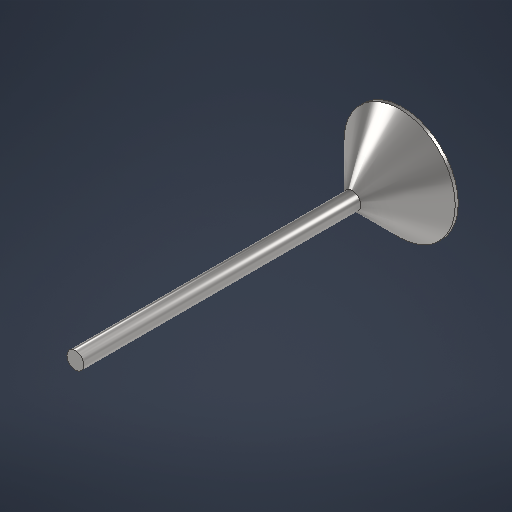
# Autodesk Inventor part: Intake_Valve
Saved by Autodesk Inventor 2027.1 (Build 311270010, 270A)
## iProperties
Created: 2026-10-17
Part Number: Intake_Valve
Material: Steel, Alloy
Document SubType Name: Modeling
Designer: kashyap
Density: 7.73 g/cm^3
Appearance: Semi-Polished
Mass: 71.2298 g
Surface Area: 41.0236 cm^2
Volume: 9.21472 cm^3
Material_Status: Assumed for this reconstruction
Author: kashyap
Autodesk Inventor part; units mm, degrees
derived "V6_Engine_Master.ipt"
ref_plane "Valve_Face_Plane" through (0, 0, 0) normal (0, 0, 1) x (1, 0, 0)
ref_plane "Valve_Margin_Plane" through (0, 0, 1) normal (0, 0, 1) x (1, 0, 0)
sketch "SK_Head" plane through (0, 0, 0) normal (0, 0, 1) x (1, 0, 0)
  circle A0 centre (0, 0) radius 18
  dimension "d21" = 36
  constraints: 1 centre point
  measures "d21" diameter of A0
extrude "Valve_Head_Margin" add sketch "SK_Head" along normal blind 1
sketch "SK_Face" plane through (0, 0, 1) normal (0, 0, 1) x (1, 0, 0)
  circle A0 centre (0, 0) radius 18
  dimension "d24" = 36
  constraints: 1 centre point
  measures "d24" diameter of A0
extrude "Valve_Seat_Face_45deg" add sketch "SK_Face" along normal blind 15.2613 draft -45
sketch "SK_Stem" plane through (0, 0, 0) normal (0, 0, 1) x (1, 0, 0)
  circle A0 centre (0, 0) radius 2.7388
  dimension "d27" = 5.4775
  constraints: 1 centre point
  measures "d27" diameter of A0
extrude "Valve_Stem" add sketch "SK_Stem" along normal blind 105.85
equation "\"d21\" = Intake_Valve_Head_Dia"
equation "\"d22\" = Valve_Margin"
equation "\"d24\" = Intake_Valve_Head_Dia"
equation "\"d26\" = -Valve_Face_Angle"
equation "\"d27\" = Intake_Valve_Stem_Dia"
equation "\"d28\" = Intake_Valve_Length"
equation "\"Intake_Valve_Head_Dia\" = 36"
equation "\"Valve_Margin\" = 1"
equation "\"Valve_Face_Angle\" = 45deg"
equation "\"Intake_Valve_Stem_Dia\" = 5.4775"
equation "\"Intake_Valve_Length\" = 105.85"
body "Solid1"
